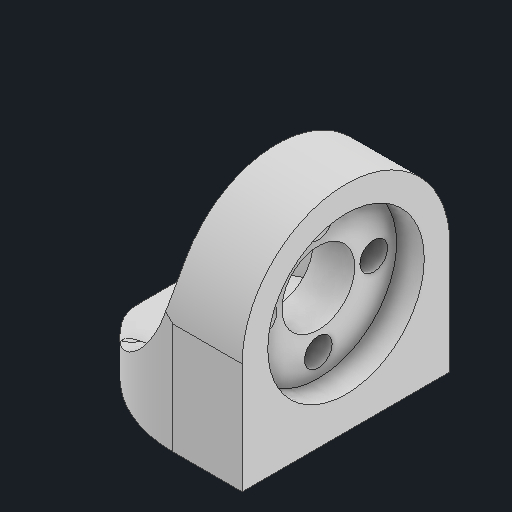
# Autodesk Inventor part: UR_rail_LeadNutHolder_v1
Saved by Autodesk Inventor 2026.2 (Build 302298000, 298)
## iProperties
Created: 2025-11-14
Part Number: UR_rail_LeadNutHolder_v1
Material: 일반
Document SubType Name: Modeling
Designer: work
Density: 1 g/cm^3
Appearance: 기본값
Author: work
Autodesk Inventor part; units mm, degrees
ref_plane "YZ Plane" through (0, 0, 0) normal (1, 0, 0) x (0, 1, 0)
ref_plane "XZ Plane" through (0, 0, 0) normal (0, 1, 0) x (-1, 0, 0)
ref_plane "XY Plane" through (0, 0, 0) normal (0, 0, 1) x (1, 0, 0)
sketch "스케치1" plane through (0, 0, 0) normal (0, 1, 0) x (-1, 0, 0)
  line L0 (0, 4) -> (0, -4) construction
  line L1 (-6, 4) -> (-6, -4)
  line L2 (6, -4) -> (6, 4)
  arc A0 (6, 4) -> (-6, 4) centre (0, 4) ccw
  arc A1 (-6, -4) -> (6, -4) centre (0, -4) ccw
  circle A2 centre (0, 4) radius 2
  circle A3 centre (0, -4) radius 2
  line L3 (-20, 15) -> (-20, -15)
  line L4 (0, 0) -> (-20, 0) construction
  line L5 (-20, 15) -> (-10, 15)
  arc A4 (4.8, 7.6) -> (-10, 15) centre (-10, -3.5) ccw
  line L6 (-20, -15) -> (-10, -15)
  arc A5 (-10, -15) -> (4.8, -7.6) centre (-10, 3.5) ccw
  point P0 (4.8, -7.6)
  dimension "d0" = 8
  dimension "d1" = 6
  dimension "d2" = 4
  dimension "d3" = 4
  dimension "d4" = 20
  dimension "d5" = 30
  dimension "d6" = 10
  constraints: 16 end point, 9 point on circle, 6 centre point, 6 tangent, 3 symmetric about line, 2 coincident, 2 midpoint, 2 vertical, 1 horizontal, 1 parallel, 1 perpendicular, 1 other
  measures "d0" distance of L0.start L0.end
  measures "d1" radius of A1
  measures "d2" diameter of A2
  measures "d3" diameter of A3
  measures "d4" distance of L4.end L4.start
  measures "d5" distance of L3.start L3.end
  measures "d6" distance of L3.start L5.end
extrude "돌출1" add sketch "스케치1" along normal blind 5
sketch "스케치2" plane through (0, 5, 0) normal (0, 1, 0) x (1, 0, 0)
  line L0 (20, -15) -> (20, 15) projected
  arc A0 (10, 15) -> (-4.8, 7.6) centre (10, -3.5) ccw projected
  line L1 (20, -15) -> (10, -15)
  line L2 (10, -15) -> (10, 15)
  line L3 (10, 15) -> (20, 15)
  line L4 (20, 15) -> (20, -15)
  line L5 (-6, 4) -> (-6, -4) projected
  arc A1 (-6, -4) -> (-4.8, -7.6) centre (0, -4) ccw projected
  arc A2 (-4.8, -7.6) -> (10, -15) centre (10, 3.5) ccw projected
  line L6 (10, -15) -> (20, -15) projected
  line L7 (20, -15) -> (20, 15) projected
  line L8 (20, 15) -> (10, 15) projected
  arc A3 (10, 15) -> (-4.8, 7.6) centre (10, -3.5) ccw projected
  arc A4 (-4.8, 7.6) -> (-6, 4) centre (0, 4) ccw projected
  circle A5 centre (0, -4) radius 2 projected
  circle A6 centre (0, 4) radius 2 projected
  line L9 (20, 0) -> (-6, 0)
  arc A7 (-3.2, -6.4) -> (10, -13) centre (10, 3.5) ccw
  arc A8 (-4, -4) -> (-3.2, -6.4) centre (0, -4) ccw
  line L10 (-4, -4) -> (-4, 4)
  arc A9 (-3.2, 6.4) -> (-4, 4) centre (0, 4) ccw
  arc A10 (10, 13) -> (-3.2, 6.4) centre (10, -3.5) ccw
  line L11 (10, 13) -> (18, 13)
  line L12 (18, 13) -> (18, -13)
  line L13 (18, -13) -> (10, -13)
  line L14 (0.5132, -10) -> (-2.6491, -10)
  line L15 (0.5132, 10) -> (-2.6491, 10)
  point P0 (0, 0)
  point P1 (-2.6491, 10)
  point P2 (10, -13)
  dimension "d26" = 2
  dimension "d27" = 10
  constraints: 22 end point, 10 point on circle, 4 centre point, 2 horizontal, 2 midpoint, 2 parallel, 2 symmetric about line, 1 perpendicular, 7 other
  measures "d26" radial gap between concentric circles of A2 A7
  measures "d27" distance between parallel lines of L9 L14
sketch "스케치3" plane through (20, 0, 15) normal (1, 0, 0) x (0, 0, -1)
  line L0 (15, 0) -> (15, 5) construction
  line L1 (19, 5) -> (11, 5) construction
  line L2 (15, 5) -> (15, 16) construction
  circle A0 centre (15, 16) radius 5.25
  circle A1 centre (15, 16) radius 15
  line L3 (0, 16) -> (0, 5)
  line L4 (0, 5) -> (30, 5) projected
  line L5 (30, 16) -> (30, 5)
  line L6 (30, 16) -> (0, 16) construction
  point P0 (0, 10.5)
  dimension "d9" = 11
  dimension "d10" = 10.5
  dimension "d11" = 30
  constraints: 10 end point, 2 centre point, 2 coincident, 2 midpoint, 2 point on circle, 2 vertical, 1 horizontal, 1 point on line
  measures "d9" distance of L0.end L2.end
  measures "d10" diameter of A0
  measures "d11" diameter of A1
extrude "돌출2" add sketch "스케치3" against normal blind 10 contours A1 L4 | L5 L4 A1 | A1 L4 L3 picked at (15.2109, 6.9294)
sketch "스케치4" plane through (20, 0, 15) normal (1, 0, 0) x (0, 0, -1)
  circle A0 centre (15, 16) radius 5.25 projected
  line L0 (0, 0) -> (30, 0) projected
  line L1 (30, 0) -> (30, 16) projected
  arc A1 (30, 16) -> (0, 16) centre (15, 16) ccw projected
  line L2 (0, 0) -> (0, 16) projected
  circle A2 centre (15, 16) radius 11.3
  point P0 (15, 0)
  dimension "d15" = 22.6
  constraints: 1 centre point, 1 coincident
  measures "d15" diameter of A2
extrude "돌출3" cut sketch "스케치4" against normal blind 4 contours A2
sketch "스케치5" plane through (16, 16, 0) normal (1, 0, 0) x (0, 0, -1)
  circle A0 centre (0, 0) radius 11.3 projected
  circle A1 centre (0, 0) radius 5.25 projected
  line L0 (0, 0) -> (0, 8) construction
  circle A2 centre (0, 8) radius 2
  circle A3 centre (-8, 0) radius 2
  circle A4 centre (0, -8) radius 2
  circle A5 centre (8, 0) radius 2
  point P0 (0, -16)
  dimension "d18" = 8
  dimension "d19" = 4
  dimension "d22" = 360
  constraints: 4 centre point, 2 end point, 1 coincident, 1 vertical, 9 other
  measures "d18" distance of L0.start L0.end
  measures "d19" diameter of A2
extrude "돌출4" cut sketch "스케치5" against normal through all contours A2 | A3 | A4 | A5
extrude "돌출5" add sketch "스케치2" along normal up to surface contours A2 L14 A7 L2 | L2 A10 L15 A0 round surface about axis through (20, 16, 0) along (-1, 0, 0) radius 15 far side no
sketch "스케치6" plane through (20, 0, -15) normal (0, 0, -1) x (-1, 0, 0)
  line L0 (0, 16) -> (0, 16) projected
  line L1 (0, 16) -> (10, 16) projected
  line L2 (19.4868, 27.1803) -> (22.6491, 27.1803) projected
  spline S0 degree 7 poles (10, 23.4833) (10.5097, 23.4833) (11.0162, 23.5152) (11.5193, 23.5783) (12.0181, 23.6709) (12.5116, 23.79) (12.9974, 23.9318) (14.23, 24.346) (14.9665, 24.6481) (15.6838, 24.9849) (16.3824, 25.3451) (17.0633, 25.7208) (17.7286, 26.1066) (18.5413, 26.5956) (18.7011, 26.6926) (18.86, 26.7899) (19.018, 26.8874) (19.1752, 26.985) (19.3315, 27.0827) (19.4868, 27.1803) knots 0 0 0 0 0 0 0 0 0.334641 0.334641 0.334641 0.334641 0.334641 0.334641 0.868465 0.868465 0.868465 0.868465 0.868465 0.868465 1 1 1 1 1 1 1 1 projected
  line L3 (10, 23.4833) -> (10, 23.4833) projected
  line L4 (22.6491, 27.1803) -> (19.4868, 27.1803) projected
  line L5 (0, 16) -> (10, 16) projected
  line L6 (10, 0) -> (24.8, 0) projected
  line L7 (24.8, 0) -> (24.8, 5) projected
  line L8 (22.6491, 5) -> (24.8, 5) projected
  line L9 (22.6491, 5) -> (22.6491, 27.1803) projected
  line L10 (10, 0) -> (10, 16) projected
  arc A0 (10, 23.4833) -> (22.6491, 5) centre (29.8288, 23.4833) ccw
  line L11 (10, 23.4833) -> (10, 31) projected
  point P0 (20, 0)
  constraints: 2 point on circle, 1 centre point, 1 tangent, 5 other
extrude "돌출6" cut sketch "스케치6" against normal through all
fillet "모깎기2" radius 2 1 edges at (-1.068, 5, -10)
fillet "모깎기3" radius 2 1 edges at (-1.068, 5, 10)
